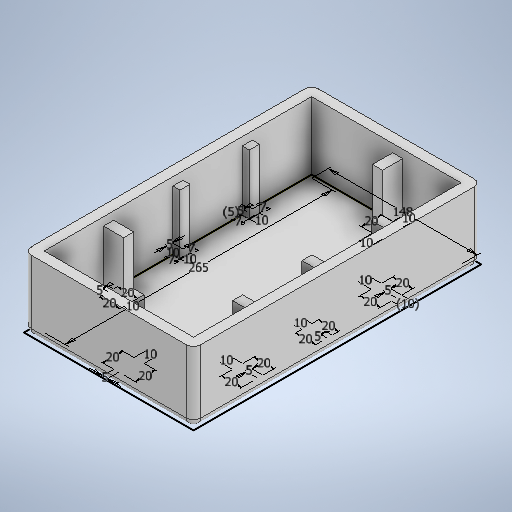
# Autodesk Inventor part: caixa
Saved by Autodesk Inventor 2025.2 (Build 292293000, 293)
## iProperties
Created: 2025-01-27
Part Number: caixa
Material: Generic
Document SubType Name: Modeling
Designer: Marcos
Density: 1 g/cm^3
Appearance: Default
Author: Marcos
Autodesk Inventor part; units mm, degrees
ref_plane "YZ Plane" through (0, 0, 0) normal (1, 0, 0) x (0, 1, 0)
ref_plane "XZ Plane" through (0, 0, 0) normal (0, 1, 0) x (-1, 0, 0)
ref_plane "XY Plane" through (0, 0, 0) normal (0, 0, 1) x (1, 0, 0)
sketch "Sketch1" plane through (0, 0, 0) normal (0, 1, 0) x (-1, 0, 0)
  line L0 (0, 0) -> (0, -265)
  line L1 (0, -265) -> (-148, -265)
  line L2 (-148, -265) -> (-148, 0)
  line L3 (-148, 0) -> (0, 0)
  line L4 (10, -275) -> (10, 10)
  line L5 (10, 10) -> (-158, 10)
  line L6 (-158, 10) -> (-158, -275)
  line L7 (-158, -275) -> (10, -275)
  dimension "d0" = 265
  dimension "d2" = 148
  dimension "d3" = 10
  constraints: 16 end point, 4 perpendicular, 1 horizontal, 1 vertical, 3 other
  measures "d0" distance of L0.start L0.end
  measures "d2" distance of L0.end L1.end
  measures "d3" distance between parallel lines of L0 L4
extrude "Extrusion1" add sketch "Sketch1" along normal blind 3 contours L0 L1 L2 L3
extrude "Extrusion2" add sketch "Sketch1" along normal blind 70
fillet "Fillet1" radius 7 4 edges at (158, 35, 10) (-10, 35, 10) (-10, 35, -275) (158, 35, -275)
fillet "Fillet2" radius 7 4 edges at (74, 0, 10) (158, 0, -132.5) (74, 0, -275) (-10, 0, -132.5)
sketch "Sketch2" plane through (0, 3, 0) normal (0, 1, 0) x (1, 0, 0)
  line L0 (148, 0) -> (148, 265) projected
  line L1 (148, 0) -> (148, 265)
  line L2 (0, 0) -> (0, 265) projected
  line L3 (148, 132.5) -> (148, 137.5)
  line L4 (148, 137.5) -> (128, 137.5)
  line L5 (128, 137.5) -> (128, 127.5)
  line L6 (128, 127.5) -> (148, 127.5)
  line L7 (148, 127.5) -> (148, 132.5)
  line L8 (0, 132.5) -> (0, 137.5)
  line L9 (0, 137.5) -> (7, 137.5)
  line L10 (7, 137.5) -> (7, 127.5)
  line L11 (7, 127.5) -> (0, 127.5)
  line L12 (0, 127.5) -> (0, 137.5)
  line L13 (0, 137.5) -> (0, 265)
  line L14 (-3, 268) -> (-3, -3) projected
  line L15 (0, 201.25) -> (0, 206.25)
  line L16 (0, 206.25) -> (7, 206.25)
  line L17 (7, 206.25) -> (7, 196.25)
  line L18 (7, 196.25) -> (0, 196.25)
  line L19 (0, 196.25) -> (0, 201.25)
  line L20 (0, 0) -> (0, 127.5)
  line L21 (0, 63.75) -> (0, 68.75)
  line L22 (0, 265) -> (0, 0) projected
  line L23 (0, 68.75) -> (20, 68.75)
  line L24 (20, 68.75) -> (20, 58.75)
  line L25 (20, 58.75) -> (0, 58.75)
  line L26 (0, 58.75) -> (0, 68.75)
  line L27 (148, 137.5) -> (148, 265)
  line L28 (148, 201.25) -> (148, 206.25)
  line L29 (148, 206.25) -> (128, 206.25)
  line L30 (128, 206.25) -> (128, 196.25)
  line L31 (128, 196.25) -> (148, 196.25)
  line L32 (148, 196.25) -> (148, 206.25)
  line L33 (148, 127.5) -> (148, 0)
  line L34 (148, 63.75) -> (148, 68.75)
  line L35 (148, 68.75) -> (128, 68.75)
  line L36 (128, 68.75) -> (128, 58.75)
  line L37 (128, 58.75) -> (148, 58.75)
  line L38 (148, 58.75) -> (148, 68.75)
  line L39 (0, 265) -> (148, 265) projected
  line L40 (0, 265) -> (148, 265)
  line L41 (0, 0) -> (148, 0)
  line L42 (148, 0) -> (0, 0) projected
  line L43 (74, 0) -> (69, 0)
  line L44 (69, 0) -> (69, 20)
  line L45 (69, 20) -> (79, 20)
  line L46 (79, 20) -> (79, 0)
  line L47 (79, 0) -> (69, 0)
  line L48 (90.3902, 265) -> (80.3902, 265)
  line L49 (80.3902, 265) -> (80.3902, 245)
  line L50 (80.3902, 245) -> (90.3902, 245)
  line L51 (151, 268) -> (-3, 268) projected
  line L52 (90.3902, 245) -> (90.3902, 265)
  point P0 (0, 68.75)
  point P1 (0, 58.75)
  point P2 (0, 206.25)
  point P3 (0, 196.25)
  point P4 (90.3902, 265)
  point P5 (80.3902, 265)
  dimension "d10" = 5
  dimension "d11" = 20
  dimension "d12" = 10
  dimension "d13" = 20
  dimension "d14" = 5
  dimension "d15" = 7
  dimension "d16" = 10
  dimension "d17" = 7
  dimension "d26" = 5
  dimension "d27" = 7
  dimension "d28" = 10
  dimension "d29" = 7
  dimension "d30" = 5
  dimension "d31" = 5
  dimension "d32" = 20
  dimension "d33" = 10
  dimension "d34" = 20
  dimension "d35" = 5
  dimension "d36" = 20
  dimension "d37" = 10
  dimension "d38" = 20
  dimension "d39" = 10
  dimension "d40" = 5
  dimension "d41" = 20
  dimension "d42" = 10
  dimension "d43" = 20
  dimension "d44" = 5
  dimension "d45" = 20
  dimension "d46" = 10
  dimension "d47" = 20
  dimension "d49" = 10
  dimension "d50" = 20
  dimension "d51" = 10
  constraints: 92 end point, 14 perpendicular, 14 point on line, 7 midpoint, 6 collinear, 4 horizontal, 1 parallel, 1 vertical, 3 other
  measures "d10" distance of L3.start L3.end
  measures "d11" distance of L3.end L4.end
  measures "d12" distance of L4.end L5.end
  measures "d13" distance of L5.end L6.end
  measures "d14" distance of L8.start L8.end
  measures "d15" distance of L8.end L9.end
  measures "d16" distance of L9.end L10.end
  measures "d17" distance of L10.end L11.end
  measures "d26" distance of L15.start L15.end
  measures "d27" distance of L15.end L16.end
  measures "d28" distance of L16.end L17.end
  measures "d29" distance of L17.end L18.end
  measures "d30" distance of L18.end L15.start
  measures "d31" distance of L21.start L21.end
  measures "d32" distance of L21.end L23.end
  measures "d33" distance of L23.end L24.end
  measures "d34" distance of L24.end L25.end
  measures "d35" distance of L28.start L28.end
  measures "d36" distance of L28.end L29.end
  measures "d37" distance of L29.end L30.end
  measures "d38" distance of L30.end L31.end
  measures "d39" distance of L31.end L28.end
  measures "d40" distance of L34.start L34.end
  measures "d41" distance of L34.end L35.end
  measures "d42" distance of L35.end L36.end
  measures "d43" distance of L36.end L37.end
  measures "d44" distance of L43.start L43.end
  measures "d45" distance of L43.end L44.end
  measures "d46" distance of L44.end L45.end
  measures "d47" distance of L45.end L46.end
  measures "d49" distance of L48.start L48.end
  measures "d50" distance of L48.end L49.end
  measures "d51" distance of L49.end L50.end
extrude "Extrusion3" add sketch "Sketch2" along normal blind 59 contours L6 L5 L4 L0
extrude "Extrusion4" add sketch "Sketch2" along normal blind 59 contours L2 L9 L10 L11
extrude "Extrusion5" add sketch "Sketch2" along normal blind 59 contours L37 L36 L35 L0 | L41 L44 L45 L46 | L6 L5 L4 L0 | L2 L23 L24 L25 | L31 L30 L29 L0 | L2 L9 L10 L11 | L52 L50 L49 L39 | L2 L16 L17 L18
body "Solid1"
